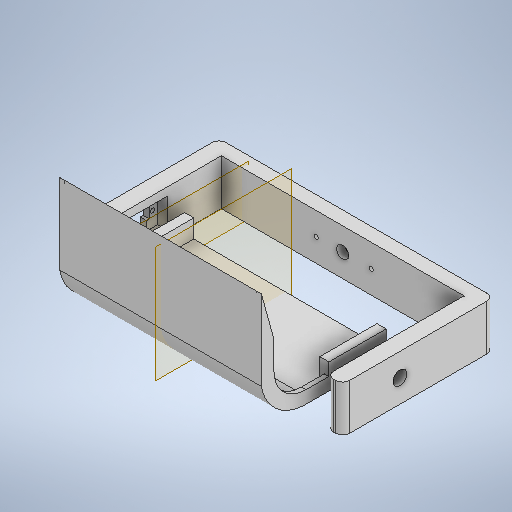
# Autodesk Inventor part: Soporte_Garra_Nuevo
Saved by Autodesk Inventor 2025.3 (Build 293356030, 356C)
## iProperties
Created: 2026-07-01
Part Number: Soporte_Garra_Nuevo
Material: Generic
Document SubType Name: Modeling
Designer: pablo
Density: 1 g/cm^3
Appearance: Default
Author: pablo
Autodesk Inventor part; units mm, degrees
ref_plane "YZ Plane" through (0, 0, 0) normal (1, 0, 0) x (0, 1, 0)
ref_plane "XZ Plane" through (0, 0, 0) normal (0, 1, 0) x (-1, 0, 0)
ref_plane "XY Plane" through (0, 0, 0) normal (0, 0, 1) x (1, 0, 0)
sketch "Sketch1" plane through (0, 0, 0) normal (0, 0, 1) x (1, 0, 0)
  line L0 (-60, 10) -> (60, 10)
  line L1 (60, 10) -> (60, -10)
  line L2 (60, -10) -> (-60, -10)
  line L3 (-60, -10) -> (-60, 10)
  point P0 (0, 0)
  point P1 (60, 0)
  point P2 (0, 10)
  dimension "d0" = 120
  dimension "d1" = 20
  constraints: 8 end point, 2 midpoint, 2 parallel, 1 horizontal, 1 horizontal alignment, 1 perpendicular, 1 vertical alignment
  measures "d0" distance of L1.end L2.end
  measures "d1" distance of L0.end L1.end
extrude "Extrusion1" add sketch "Sketch1" along normal blind 6
sketch "Sketch2" plane through (0, 0, 0) normal (0, 0, -1) x (-1, 0, 0)
  line L0 (60, -10) -> (-60, -10) projected
  line L1 (60, 10) -> (60, -10) projected
  line L2 (-60, 10) -> (60, 10) projected
  line L3 (-60, -10) -> (-60, 10) projected
  circle A0 centre (0, 0) radius 4
  circle A1 centre (-15.5, 0) radius 2
  line L4 (-0.5161, -3.9666) -> (-15.7581, -1.9833)
  line L5 (-0.5161, 3.9666) -> (-15.7581, 1.9833)
  line L6 (0, -10) -> (0, 10)
  circle A2 centre (15.5, 0) radius 2
  line L7 (0.5161, -3.9666) -> (15.7581, -1.9833)
  line L8 (0.5161, 3.9666) -> (15.7581, 1.9833)
  point P0 (0.5161, -3.9666)
  point P1 (0.5161, 3.9666)
  dimension "d4" = 8
  dimension "d5" = 4
  dimension "d6" = 15.5
  constraints: 10 end point, 6 point on circle, 5 symmetric about line, 4 tangent, 3 centre point, 2 coincident, 2 midpoint, 1 horizontal alignment, 1 other
  measures "d4" diameter of A0
  measures "d5" diameter of A1
  measures "d6" distance of point (0, 0) A1.centre
extrude "Extrusion2" cut sketch "Sketch2" against normal blind 2.5 contours L6 A0 | A0 L6 | L4 A1 L5 A0 | A0 L8 A2 L7 | A1 | A2
sketch "Sketch3" plane through (0, 0, 6) normal (0, 0, 1) x (1, 0, 0)
  point P0 (0, 0)
  point P1 (0, 0)
  constraints: 1 coincident
hole "Hole1" at (0, 0, 6) direction (0, 0, -1) diameter 5.3 depth 3.5
sketch "Sketch4" plane through (0, 0, 2.5) normal (0, 0, -1) x (-1, 0, 0)
  arc A0 (-0.5161, -3.9666) -> (0.5161, -3.9666) centre (0, 0) ccw projected
  line L0 (-0.5161, -3.9666) -> (-15.7581, -1.9833) projected
  arc A1 (-15.7581, 1.9833) -> (-15.7581, -1.9833) centre (-15.5, 0) ccw projected
  line L1 (-15.7581, 1.9833) -> (-0.5161, 3.9666) projected
  arc A2 (0.5161, 3.9666) -> (-0.5161, 3.9666) centre (0, 0) ccw projected
  line L2 (0.5161, 3.9666) -> (15.7581, 1.9833) projected
  arc A3 (15.7581, -1.9833) -> (15.7581, 1.9833) centre (15.5, 0) ccw projected
  line L3 (15.7581, -1.9833) -> (0.5161, -3.9666) projected
  line L4 (60, -10) -> (-60, -10) projected
  line L5 (60, 10) -> (60, -10) projected
  line L6 (-60, 10) -> (60, 10) projected
  line L7 (-60, -10) -> (-60, 10) projected
  point P0 (11.5278, 0)
  point P1 (-12.4722, 0)
  dimension "d16" = 24
  constraints: 2 horizontal alignment
  measures "d16" distance of point (-12.472, 0) point (11.528, 0)
hole "Hole2" at (-11.5278, 0, 2.5) at (12.4722, 0, 2.5) direction (0, 0, 1) diameter 1.9 depth 3.5
sketch "Sketch5" plane through (0, 0, 6) normal (0, 0, 1) x (1, 0, 0)
  circle A0 centre (12.4722, 0) radius 0.95 projected
  circle A1 centre (-11.5278, 0) radius 0.95 projected
  circle A2 centre (0, 0) radius 2.65 projected
  line L0 (-60, -10) -> (60, -10) projected
  line L1 (60, -10) -> (60, 10) projected
  line L2 (60, 10) -> (-60, 10) projected
  line L3 (-60, 10) -> (-60, -10) projected
  line L4 (-53, 10) -> (-53, -10)
  line L5 (-60, -10) -> (60, -10) projected
  line L6 (53, -10) -> (53, 10)
  dimension "d24" = 7
  dimension "d25" = 7
  constraints: 4 end point, 4 point on line, 2 perpendicular
  measures "d24" distance between parallel lines of L1 L6
  measures "d25" distance between parallel lines of L3 L4
extrude "Extrusion3" add sketch "Sketch5" along normal blind 60 contours L3 L2 L4 L0 | L6 L2 L1 L0
sketch "Sketch6" plane through (-60, -10, 0) normal (-1, 0, 0) x (0, 0, 1)
  line L0 (0, 20) -> (0, 0) projected
  line L1 (0, 0) -> (66, 0) projected
  line L2 (66, 20) -> (66, 0) projected
  line L3 (0, 20) -> (66, 20) projected
  line L4 (57.6, 3.5) -> (34.4, 3.5)
  line L5 (34.4, 3.5) -> (34.4, 16.5)
  line L6 (34.4, 16.5) -> (57.6, 16.5)
  line L7 (57.6, 16.5) -> (57.6, 3.5)
  point P0 (0, 10)
  point P1 (46, 16.5)
  point P2 (57.6, 10)
  point P3 (66, 10)
  dimension "d28" = 13
  dimension "d29" = 23.2
  dimension "d30" = 20
  constraints: 8 end point, 3 midpoint, 2 parallel, 1 horizontal, 1 horizontal alignment, 1 perpendicular
  measures "d28" distance of L6.end L4.start
  measures "d29" distance of L5.end L6.end
  measures "d30" distance from line of L2 point (46, 16.5)
extrude "Extrusion4" cut sketch "Sketch6" against normal up to surface (7 mm away) contours L4 L5 L6 L7
sketch "Sketch7" plane through (-53, -10, 6) normal (1, 0, 0) x (0, 0, -1)
  line L0 (-51.6, 3.5) -> (-51.6, 16.5) projected
  line L1 (-51.6, 16.5) -> (-28.4, 16.5) projected
  line L2 (-28.4, 16.5) -> (-28.4, 3.5) projected
  line L3 (-28.4, 3.5) -> (-51.6, 3.5) projected
  line L4 (0, 20) -> (0, 0) projected
  line L5 (0, 20) -> (-60, 20) projected
  line L6 (-60, 0) -> (-60, 20) projected
  line L7 (0, 0) -> (-60, 0) projected
  line L8 (-28.4, 3.5) -> (-23.5, 3.5)
  line L9 (-23.5, 3.5) -> (-23.5, 16.5)
  line L10 (-23.5, 16.5) -> (-28.4, 16.5)
  line L11 (-28.4, 16.5) -> (-28.4, 3.5)
  line L12 (-51.6, 16.5) -> (-56.5, 16.5)
  line L13 (-56.5, 16.5) -> (-56.5, 3.5)
  line L14 (-56.5, 3.5) -> (-51.6, 3.5)
  line L15 (-51.6, 3.5) -> (-51.6, 16.5)
  point P0 (6, 10)
  dimension "d33" = 33
  constraints: 16 end point, 4 parallel, 2 equal length, 2 horizontal, 2 perpendicular, 1 point on line
  measures "d33" distance between parallel lines of L9 L13
extrude "Extrusion5" cut sketch "Sketch7" against normal blind 4.3 contours L14 L13 L12 L0 | L2 L10 L9 L8
sketch "Sketch8" plane through (-60, -10, 0) normal (-1, 0, 0) x (0, 0, 1)
  line L0 (57.6, 16.5) -> (57.6, 3.5) projected
  line L1 (57.6, 3.5) -> (34.4, 3.5) projected
  line L2 (34.4, 3.5) -> (34.4, 16.5) projected
  line L3 (34.4, 16.5) -> (57.6, 16.5) projected
  line L4 (0, 20) -> (0, 0) projected
  line L5 (0, 0) -> (66, 0) projected
  line L6 (66, 20) -> (66, 0) projected
  line L7 (0, 20) -> (66, 20) projected
  point P0 (0, 10)
  point P1 (31.75, 10)
  point P2 (60.25, 10)
  point P3 (57.6, 10)
  point P4 (34.4, 10)
  point P5 (46, 16.5)
  dimension "d36" = 28.5
  dimension "d37" = 14.25
  constraints: 3 midpoint, 2 horizontal alignment
  measures "d36" distance of point (31.75, 10) point (60.25, 10)
  measures "d37" horizontal distance of point (46, 16.5) point (60.25, 10)
hole "Hole3" at (-60, 0, 31.75) at (-60, 0, 60.25) direction (1, 0, 0) diameter 1.9 depth 2.7
sketch "Sketch9" plane through (53, -10, 6) normal (-1, 0, 0) x (0, 0, 1)
  line L0 (51.6, 16.5) -> (51.6, 3.5) projected
  point P0 (-6, 10)
  point P1 (35, 10)
  point P2 (51.6, 10)
  dimension "d45" = 16.6
  constraints: 1 horizontal alignment, 1 midpoint
  measures "d45" distance from line of point (35, 10) L0
hole "Hole4" at (53, 0, 41) direction (1, 0, 0) diameter 6 depth 7
fillet "Fillet1" radius 3 6 edges at (-60, 0, 0) (60, 0, 0) (60, 0, 66) (53, 0, 66) (-53, 0, 66) (-60, 0, 66)
sketch "Sketch10" plane through (-57.3, -10, 6) normal (1, 0, 0) x (0, 0, -1)
  circle A0 centre (-25.75, 10) radius 0.95 projected
  line L0 (-23.5, 16.5) -> (-23.5, 3.5) projected
  line L1 (-28.4, 16.5) -> (-23.5, 16.5) projected
  line L2 (-28.4, 3.5) -> (-28.4, 16.5) projected
  line L3 (-23.5, 3.5) -> (-28.4, 3.5) projected
  line L4 (-28.4, 12.5) -> (-27.1, 12.5)
  line L5 (-27.1, 12.5) -> (-27.1, 7.5)
  line L6 (-27.1, 7.5) -> (-28.4, 7.5)
  line L7 (-28.4, 7.5) -> (-28.4, 12.5)
  point P0 (6, 10)
  point P1 (-27.1, 10)
  point P2 (-28.4, 10)
  dimension "d54" = 1.3
  dimension "d55" = 5
  constraints: 8 end point, 2 midpoint, 2 parallel, 1 horizontal, 1 horizontal alignment, 1 perpendicular, 1 point on line
  measures "d54" distance of L5.end L6.end
  measures "d55" distance of L4.end L5.end
extrude "Extrusion6" cut sketch "Sketch10" against normal up to surface (2.7 mm away) contours L4 L5 L6 L2
ref_plane "Work Plane1" through (-44, -10, 6) normal (1, 0, 0) x (0, 0, -1)
sketch "Sketch11" plane through (-44, -10, 6) normal (1, 0, 0) x (0, 0, -1)
  circle A0 centre (-35, 10) radius 3 projected
  circle A1 centre (-35, 10) radius 4
  line L0 (-25, 4.5) -> (-50, 4.5)
  line L1 (-50, 4.5) -> (-50, 15.5)
  line L2 (-50, 15.5) -> (-25, 15.5)
  line L3 (-25, 15.5) -> (-25, 4.5)
  point P0 (6, 10)
  point P1 (-25, 10)
  dimension "d59" = 8
  dimension "d60" = 11
  dimension "d61" = 10
  dimension "d62" = 25
  constraints: 8 end point, 2 parallel, 1 centre point, 1 coincident, 1 horizontal, 1 horizontal alignment, 1 midpoint, 1 perpendicular
  measures "d59" diameter of A1
  measures "d60" distance of L2.end L0.start
  measures "d61" distance from line of A0.centre L3
  measures "d62" distance of L0.start L0.end
extrude "Extrusion8" add sketch "Sketch11" along normal blind 4 separate body contours A0 | A1 | L0 L1 L2 L3
sketch "Sketch13" plane through (-40, -10, 6) normal (1, 0, 0) x (0, 0, -1)
  line L0 (-25, 15.5) -> (-50, 15.5) projected
  line L1 (-50, 15.5) -> (-50, 4.5) projected
  line L2 (-50, 4.5) -> (-25, 4.5) projected
  line L3 (-25, 4.5) -> (-25, 15.5) projected
  line L4 (-25, 4.5) -> (-60, 4.5)
  line L5 (-60, 4.5) -> (-60, 7.5)
  line L6 (-60, 7.5) -> (-25, 7.5)
  line L7 (-25, 7.5) -> (-25, 4.5)
  line L8 (-60, 20) -> (-60, 0) projected
  arc A0 (-76.5, 21) -> (-60, 7.5) centre (-60, 24.3333) ccw
  arc A1 (-79.5, 21) -> (-60, 4.5) centre (-60, 24.2727) ccw
  line L9 (-79.5, 21) -> (-76.5, 21)
  line L10 (-79.5, 21) -> (-79.5, 36)
  line L11 (-76.5, 21) -> (-76.5, 36)
  line L12 (-76.5, 36) -> (-79.5, 36)
  line L13 (-79.5, 36) -> (-79.5, 56)
  line L14 (-79.5, 56) -> (-76.5, 36)
  point P0 (6, 10)
  point P1 (-60, 6)
  point P2 (-78, 21)
  dimension "d68" = 3
  dimension "d71" = 3
  dimension "d74" = 18
  dimension "d75" = 15
  dimension "d76" = 15
  dimension "d77" = 20
  constraints: 20 end point, 4 point on circle, 3 vertical, 2 centre point, 2 horizontal, 2 midpoint, 2 parallel, 2 perpendicular, 2 tangent, 1 vertical alignment
  measures "d68" distance between parallel lines of L4 L6
  measures "d71" distance of L9.start L9.end
  measures "d74" horizontal distance of L5.end point (-78, 21)
  measures "d75" vertical distance of point (-60, 6) point (-78, 21)
  measures "d76" distance of L9.end L11.end
  measures "d77" distance of L10.end L13.end
extrude "Extrusion9" add sketch "Sketch13" along normal blind 40 contours L3 L2 L1 L6 | L1 L4 L5 L6 | L5 A1 L9 A0 | L9 L10 L12 L11 | L12 L13 L14 bodies 2
sketch "Sketch14" plane through (-40, -10, 6) normal (-1, 0, 0) x (0, 0, 1)
  line L0 (60, 4.5) -> (50, 4.5) projected
  arc A0 (60, 4.5) -> (79.5, 21) centre (60, 24.2727) ccw projected
  line L1 (79.5, 56) -> (79.5, 21) projected
  line L2 (76.5, 36) -> (79.5, 56) projected
  line L3 (76.5, 21) -> (76.5, 36) projected
  arc A1 (60, 7.5) -> (76.5, 21) centre (60, 24.3333) ccw projected
  line L4 (50, 7.5) -> (60, 7.5) projected
  line L5 (50, 15.5) -> (50, 4.5) projected
  line L6 (50, 4.5) -> (50, 7.5)
  line L7 (50, 7.5) -> (50, 4.5) projected
  point P0 (-6, 10)
  constraints: 2 end point, 2 point on line
extrude "Extrusion10" add sketch "Sketch14" along normal up to surface (4 mm away) bodies 2
ref_plane "Work Plane3" through (0, -10, 6) normal (1, 0, 0) x (0, 0, -1)
sketch "Sketch16" plane through (-44, -10, 6) normal (-1, 0, 0) x (0, 0, 1)
  line L0 (50, 10) -> (60, 10)
  line L1 (50, 15.5) -> (50, 7.5) projected
  line L2 (60, 7.5) -> (50, 7.5) projected
  arc A0 (60, 10) -> (74, 24) centre (60, 24) ccw
  line L3 (74, 24) -> (74, 36)
  line L4 (25, 15.5) -> (50, 15.5) projected
  line L5 (25, 4.5) -> (25, 15.5) projected
  line L6 (25, 4.5) -> (60, 4.5) projected
  arc A1 (60, 4.5) -> (79.5, 21) centre (60, 24.2727) ccw projected
  line L7 (79.5, 21) -> (79.5, 56) projected
  line L8 (79.5, 56) -> (76.5, 36) projected
  line L9 (76.5, 36) -> (76.5, 21) projected
  arc A2 (60, 7.5) -> (76.5, 21) centre (60, 24.3333) ccw projected
  line L10 (60, 7.5) -> (50, 7.5) projected
  line L11 (50, 15.5) -> (50, 7.5) projected
  line L12 (74, 36) -> (79.5, 56)
  point P0 (-6, 10)
  point P1 (60, 7.5)
  dimension "d87" = 2.5
  dimension "d88" = 2.5
  constraints: 6 end point, 2 point on circle, 2 tangent, 1 centre point, 1 horizontal, 1 horizontal alignment, 1 point on line, 1 vertical, 1 vertical alignment
  measures "d87" distance between parallel lines of L2 L0
  measures "d88" distance between parallel lines of L9 L3
extrude "Extrusion12" add sketch "Sketch16" against normal blind 2 contours L0 A0 L3 L12 L8 L9 A2 L2 L1 bodies 2
mirror "Mirror2" about plane through (0, -10, 6) normal (1, 0, 0) of "Extrusion8", "Extrusion9", "Extrusion10", "Extrusion12" bodies 2
equation "\"d37\" = 0.5 * d36"
body "Solid1"
